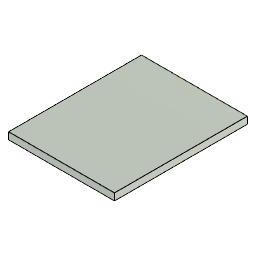
T8 lead + MGN12 construction X axis (Autodesk Fusion 360 archive; units mm, degrees)
design "plate"
Autodesk Fusion 360 part; units mm, degrees
sketch "Sketch1" plane through (0, 0, 0) normal (0, 0, 1) x (1, 0, 0)
  line L0 (70.0675, 75.402) -> (-70.0675, 75.402)
  line L1 (-70.0675, 75.402) -> (-70.0675, -75.402)
  line L2 (-70.0675, -75.402) -> (70.0675, -75.402)
  line L3 (70.0675, -75.402) -> (70.0675, 75.402)
  line L4 (70.0675, 75.402) -> (-70.0675, -75.402) construction
  line L5 (-70.0675, 75.402) -> (70.0675, -75.402) construction
  constraint horizontal L0
  constraint perpendicular L0 L1
  constraint parallel L0 L2
  constraint parallel L1 L3
  constraint coincident L4 origin
  constraint coincident L5 origin
extrude "Extrude1" add sketch "Sketch1" along normal blind 8
move_face "OffsetFaces1" offset -10 1 faces at (70.0675, -25.134, 5.3333)
move_face "OffsetFaces2" offset -10 1 faces at (-70.0675, 25.134, 5.3333)

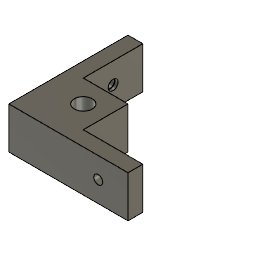
design "brecet corner"
Autodesk Fusion 360 part; units mm, degrees
sketch "Sketch1" plane through (0, 0, 0) normal (0, 0, 1) x (1, 0, 0)
  line L0 (0, 0) -> (5, 0)
  line L1 (5, 0) -> (5, 40)
  line L2 (5, 40) -> (0, 40)
  line L3 (0, 40) -> (0, 0)
  line L4 (0, 0) -> (40, 0)
  line L5 (40, 0) -> (40, 5)
  line L6 (40, 5) -> (0, 5)
  line L7 (0, 5) -> (0, 0)
  line L8 (5, 5) -> (20, 5)
  line L9 (20, 5) -> (20, 20)
  line L10 (20, 20) -> (5, 20)
  line L11 (5, 20) -> (5, 5)
  dimension "d1" = 40
  constraint horizontal L0
  constraint vertical L1
  constraint horizontal L2
  constraint vertical L3
  constraint coincident L0.start L3.end
  constraint horizontal L4
  constraint vertical L5
  constraint horizontal L6
  constraint vertical L7
  constraint horizontal L8
  constraint vertical L9
  constraint horizontal L10
  constraint vertical L11
  constraint coincident L6 L8.start
  constraint coincident L1 L8.start
  measures "d1" distance of L0.start L2.end
extrude "Extrude1" add sketch "Sketch1" along normal blind 14
sketch "Sketch2" plane through (5, 0, 0) normal (1, 0, 0) x (0, 1, 0)
  line L0 (20, 0) -> (40, 0)
  line L1 (40, 0) -> (40, 14)
  line L2 (40, 14) -> (20, 14)
  line L3 (20, 14) -> (20, 0)
  point P0 (30, 7)
hole "Hole1" at (5, 30, 7) direction (-1, 0, 0) diameter 3 depth 5.5 tip angle 118 counterbore diameter 3.3 counterbore depth 1
sketch "Sketch3" plane through (0, 5, 0) normal (0, 1, 0) x (-1, 0, 0)
  line L0 (-40, 0) -> (-20, 0)
  line L1 (-20, 0) -> (-20, 14)
  line L2 (-20, 14) -> (-40, 14)
  line L3 (-40, 14) -> (-40, 0)
  point P0 (-30, 7)
hole "Hole2" at (30, 5, 7) direction (0, -1, 0) diameter 3 depth 5.5 tip angle 180 counterbore diameter 4 counterbore depth 2
sketch "Sketch4" plane through (0, 0, 14) normal (0, 0, 1) x (-1, 0, 0)
  line L0 (-20, -20) -> (-5, -20)
  line L1 (-5, -20) -> (-5, -40)
  line L2 (-5, -40) -> (0, -40)
  line L3 (0, -40) -> (0, 0)
  line L4 (0, 0) -> (-40, 0)
  line L5 (-40, 0) -> (-40, -5)
  line L6 (-40, -5) -> (-20, -5)
  line L7 (-20, -5) -> (-20, -20)
  point P0 (-12.5, -12.5)
hole "Hole3" at (12.5, 12.5, 14) direction (0, 0, -1) diameter 6 depth 6 tip angle 180
hole "Hole4" at (12.5, 12.5, 8) direction (0, 0, -1) diameter 6 depth 14 tip angle 180
